Autodesk Fusion 360 part; units mm, degrees
(part 3 of 3)
sketch "Sketch9" plane through (0, 0, 32.4334) normal (0, 0, -1) x (1, 0, 0)
  circle A0 centre (290.8949, -267.5741) radius 1.5
  line L0 (337.7884, -328.2178) -> (337.7884, -325.2178)
  line L1 (337.7884, -325.2178) -> (343.7884, -325.2178)
  line L2 (343.7884, -325.2178) -> (343.7884, -322.2178)
  line L3 (343.7884, -322.2178) -> (349.7884, -322.2178)
  line L4 (349.7884, -322.2178) -> (349.7884, -319.2178)
  line L5 (349.7884, -319.2178) -> (358.7884, -319.2178)
  line L6 (358.7884, -319.2178) -> (358.7884, -316.2178)
  line L7 (358.7884, -316.2178) -> (370.7884, -316.2178)
  line L8 (370.7884, -316.2178) -> (370.7884, -313.2178)
  line L9 (370.7884, -313.2178) -> (408.7884, -313.2178)
  line L10 (408.7884, -313.2178) -> (408.7884, -316.2178)
  line L11 (408.7884, -316.2178) -> (420.7885, -316.2178)
  line L12 (420.7885, -316.2178) -> (420.7885, -319.2178)
  line L13 (420.7885, -319.2178) -> (429.7885, -319.2178)
  line L14 (429.7885, -319.2178) -> (429.7885, -322.2178)
  line L15 (429.7885, -322.2178) -> (435.7885, -322.2178)
  line L16 (435.7885, -322.2178) -> (435.7885, -325.2178)
  line L17 (435.7885, -325.2178) -> (441.7885, -325.2178)
  line L18 (441.7885, -325.2178) -> (441.7885, -328.2178)
  line L19 (441.7885, -328.2178) -> (444.7885, -328.2178)
  line L20 (444.7885, -328.2178) -> (444.7885, -331.2178)
  line L21 (444.7885, -331.2178) -> (459.7885, -331.2178)
  line L22 (459.7885, -331.2178) -> (459.7885, -328.2178)
  line L23 (459.7885, -328.2178) -> (462.7885, -328.2178)
  line L24 (462.7885, -328.2178) -> (462.7885, -325.2178)
  line L25 (462.7885, -325.2178) -> (465.7885, -325.2178)
  line L26 (465.7885, -325.2178) -> (465.7885, -319.2178)
  line L27 (465.7885, -319.2178) -> (468.7885, -319.2178)
  line L28 (468.7885, -319.2178) -> (468.7885, -310.2178)
  line L29 (468.7885, -310.2178) -> (471.7885, -310.2178)
  line L30 (471.7885, -310.2178) -> (471.7885, -307.2178)
  line L31 (471.7885, -307.2178) -> (474.7885, -307.2178)
  line L32 (474.7885, -307.2178) -> (474.7885, -304.2178)
  line L33 (474.7885, -304.2178) -> (477.7885, -304.2178)
  line L34 (477.7885, -304.2178) -> (477.7885, -298.2178)
  line L35 (477.7885, -298.2178) -> (480.7885, -298.2178)
  line L36 (480.7885, -298.2178) -> (480.7885, -289.2178)
  line L37 (480.7885, -289.2178) -> (483.7885, -289.2178)
  line L38 (483.7885, -289.2178) -> (483.7885, -277.2178)
  line L39 (483.7885, -277.2178) -> (486.7885, -277.2178)
  line L40 (486.7885, -277.2178) -> (486.7885, -256.2178)
  line L41 (486.7885, -256.2178) -> (489.7885, -256.2178)
  line L42 (489.7885, -256.2178) -> (489.7885, -238.2178)
  line L43 (489.7885, -238.2178) -> (486.7885, -238.2178)
  line L44 (486.7885, -238.2178) -> (486.7885, -229.2178)
  line L45 (486.7885, -229.2178) -> (483.7885, -229.2178)
  line L46 (483.7885, -229.2178) -> (483.7885, -226.2178)
  line L47 (483.7885, -226.2178) -> (480.7885, -226.2178)
  line L48 (480.7885, -226.2178) -> (480.7885, -223.2178)
  line L49 (480.7885, -223.2178) -> (477.7885, -223.2178)
  line L50 (477.7885, -223.2178) -> (477.7885, -220.2178)
  line L51 (477.7885, -220.2178) -> (459.7885, -220.2178)
  line L52 (459.7885, -220.2178) -> (459.7885, -223.2178)
  line L53 (459.7885, -223.2178) -> (456.7885, -223.2178)
  line L54 (456.7885, -223.2178) -> (456.7885, -226.2178)
  line L55 (456.7885, -226.2178) -> (453.7885, -226.2178)
  line L56 (453.7885, -226.2178) -> (453.7885, -229.2178)
  line L57 (453.7885, -229.2178) -> (450.7885, -229.2178)
  line L58 (450.7885, -229.2178) -> (450.7885, -232.2178)
  line L59 (450.7885, -232.2178) -> (447.7885, -232.2178)
  line L60 (447.7885, -232.2178) -> (447.7885, -238.2178)
  line L61 (447.7885, -238.2178) -> (444.7885, -238.2178)
  line L62 (444.7885, -238.2178) -> (444.7885, -244.2178)
  line L63 (444.7885, -244.2178) -> (441.7885, -244.2178)
  line L64 (441.7885, -244.2178) -> (441.7885, -247.2178)
  line L65 (441.7885, -247.2178) -> (438.7885, -247.2178)
  line L66 (438.7885, -247.2178) -> (438.7885, -250.2178)
  line L67 (438.7885, -250.2178) -> (435.7885, -250.2178)
  line L68 (435.7885, -250.2178) -> (435.7885, -253.2178)
  line L69 (435.7885, -253.2178) -> (343.7884, -253.2178)
  line L70 (343.7884, -253.2178) -> (343.7884, -250.2178)
  line L71 (343.7884, -250.2178) -> (340.7884, -250.2178)
  line L72 (340.7884, -250.2178) -> (340.7884, -247.2178)
  line L73 (340.7884, -247.2178) -> (337.7884, -247.2178)
  line L74 (337.7884, -247.2178) -> (337.7884, -244.2178)
  line L75 (337.7884, -244.2178) -> (334.7884, -244.2178)
  line L76 (334.7884, -244.2178) -> (334.7884, -238.2178)
  line L77 (334.7884, -238.2178) -> (331.7884, -238.2178)
  line L78 (331.7884, -238.2178) -> (331.7884, -232.2178)
  line L79 (331.7884, -232.2178) -> (328.7884, -232.2178)
  line L80 (328.7884, -232.2178) -> (328.7884, -229.2178)
  line L81 (328.7884, -229.2178) -> (325.7884, -229.2178)
  line L82 (325.7884, -229.2178) -> (325.7884, -226.2178)
  line L83 (325.7884, -226.2178) -> (322.7884, -226.2178)
  line L84 (322.7884, -226.2178) -> (322.7884, -223.2178)
  line L85 (322.7884, -223.2178) -> (319.7884, -223.2178)
  line L86 (319.7884, -223.2178) -> (319.7884, -220.2178)
  line L87 (319.7884, -220.2178) -> (301.7884, -220.2178)
  line L88 (301.7884, -220.2178) -> (301.7884, -223.2178)
  line L89 (301.7884, -223.2178) -> (298.7884, -223.2178)
  line L90 (298.7884, -223.2178) -> (298.7884, -226.2178)
  line L91 (298.7884, -226.2178) -> (295.7884, -226.2178)
  line L92 (295.7884, -226.2178) -> (295.7884, -229.2178)
  line L93 (295.7884, -229.2178) -> (292.7884, -229.2178)
  line L94 (292.7884, -229.2178) -> (292.7884, -238.2178)
  line L95 (292.7884, -238.2178) -> (289.7884, -238.2178)
  line L96 (289.7884, -238.2178) -> (289.7884, -256.2178)
  line L97 (289.7884, -256.2178) -> (292.7884, -256.2178)
  line L98 (292.7884, -256.2178) -> (292.7884, -266.2145)
  arc A1 (292.7884, -266.2145) -> (292.7884, -268.9337) centre (290.8949, -267.5741) ccw
  line L99 (292.7884, -268.9337) -> (292.7884, -277.2178)
  line L100 (292.7884, -277.2178) -> (295.7884, -277.2178)
  line L101 (295.7884, -277.2178) -> (295.7884, -289.2178)
  line L102 (295.7884, -289.2178) -> (298.7884, -289.2178)
  line L103 (298.7884, -289.2178) -> (298.7884, -298.2178)
  line L104 (298.7884, -298.2178) -> (301.7884, -298.2178)
  line L105 (301.7884, -298.2178) -> (301.7884, -304.2178)
  line L106 (301.7884, -304.2178) -> (304.7884, -304.2178)
  line L107 (304.7884, -304.2178) -> (304.7884, -307.2178)
  line L108 (304.7884, -307.2178) -> (307.7884, -307.2178)
  line L109 (307.7884, -307.2178) -> (307.7884, -310.2178)
  line L110 (307.7884, -310.2178) -> (310.7884, -310.2178)
  line L111 (310.7884, -310.2178) -> (310.7884, -319.2178)
  line L112 (310.7884, -319.2178) -> (313.7884, -319.2178)
  line L113 (313.7884, -319.2178) -> (313.7884, -325.2178)
  line L114 (313.7884, -325.2178) -> (316.7884, -325.2178)
  line L115 (316.7884, -325.2178) -> (316.7884, -328.2178)
  line L116 (316.7884, -328.2178) -> (319.7884, -328.2178)
  line L117 (319.7884, -328.2178) -> (319.7884, -331.2178)
  line L118 (319.7884, -331.2178) -> (334.7884, -331.2178)
  line L119 (334.7884, -331.2178) -> (334.7884, -328.2178)
  line L120 (334.7884, -328.2178) -> (337.7884, -328.2178)
  line L121 (336.7884, -324.2178) -> (336.7884, -327.2178)
  line L122 (336.7884, -327.2178) -> (333.7884, -327.2178)
  line L123 (333.7884, -327.2178) -> (333.7884, -330.2178)
  line L124 (333.7884, -330.2178) -> (320.7884, -330.2178)
  line L125 (320.7884, -330.2178) -> (320.7884, -327.2178)
  line L126 (320.7884, -327.2178) -> (317.7884, -327.2178)
  line L127 (317.7884, -327.2178) -> (317.7884, -324.2178)
  line L128 (317.7884, -324.2178) -> (314.7884, -324.2178)
  line L129 (314.7884, -324.2178) -> (314.7884, -318.2178)
  line L130 (314.7884, -318.2178) -> (311.7884, -318.2178)
  line L131 (311.7884, -318.2178) -> (311.7884, -309.2178)
  line L132 (311.7884, -309.2178) -> (308.7884, -309.2178)
  line L133 (308.7884, -309.2178) -> (308.7884, -306.2178)
  line L134 (308.7884, -306.2178) -> (305.7884, -306.2178)
  line L135 (305.7884, -306.2178) -> (305.7884, -303.2178)
  line L136 (305.7884, -303.2178) -> (302.7884, -303.2178)
  line L137 (302.7884, -303.2178) -> (302.7884, -297.2178)
  line L138 (302.7884, -297.2178) -> (299.7884, -297.2178)
  line L139 (299.7884, -297.2178) -> (299.7884, -288.2178)
  line L140 (299.7884, -288.2178) -> (296.7884, -288.2178)
  line L141 (296.7884, -288.2178) -> (296.7884, -276.2178)
  line L142 (296.7884, -276.2178) -> (293.7884, -276.2178)
  line L143 (293.7884, -276.2178) -> (293.7884, -255.2178)
  line L144 (293.7884, -255.2178) -> (290.7884, -255.2178)
  line L145 (290.7884, -255.2178) -> (290.7884, -239.2178)
  line L146 (290.7884, -239.2178) -> (293.7884, -239.2178)
  line L147 (293.7884, -239.2178) -> (293.7884, -230.2178)
  line L148 (293.7884, -230.2178) -> (296.7884, -230.2178)
  line L149 (296.7884, -230.2178) -> (296.7884, -227.2178)
  line L150 (296.7884, -227.2178) -> (299.7884, -227.2178)
  line L151 (299.7884, -227.2178) -> (299.7884, -224.2178)
  line L152 (299.7884, -224.2178) -> (302.7884, -224.2178)
  line L153 (302.7884, -224.2178) -> (302.7884, -221.2178)
  line L154 (302.7884, -221.2178) -> (318.7884, -221.2178)
  line L155 (318.7884, -221.2178) -> (318.7884, -224.2178)
  line L156 (318.7884, -224.2178) -> (321.7884, -224.2178)
  line L157 (321.7884, -224.2178) -> (321.7884, -227.2178)
  line L158 (321.7884, -227.2178) -> (324.7884, -227.2178)
  line L159 (324.7884, -227.2178) -> (324.7884, -230.2178)
  line L160 (324.7884, -230.2178) -> (327.7884, -230.2178)
  line L161 (327.7884, -230.2178) -> (327.7884, -233.2178)
  line L162 (327.7884, -233.2178) -> (330.7884, -233.2178)
  line L163 (330.7884, -233.2178) -> (330.7884, -239.2178)
  line L164 (330.7884, -239.2178) -> (333.7884, -239.2178)
  line L165 (333.7884, -239.2178) -> (333.7884, -245.2178)
  line L166 (333.7884, -245.2178) -> (336.7884, -245.2178)
  line L167 (336.7884, -245.2178) -> (336.7884, -248.2178)
  line L168 (336.7884, -248.2178) -> (339.7884, -248.2178)
  line L169 (339.7884, -248.2178) -> (339.7884, -251.2178)
  line L170 (339.7884, -251.2178) -> (342.7884, -251.2178)
  line L171 (342.7884, -251.2178) -> (342.7884, -254.2178)
  line L172 (342.7884, -254.2178) -> (436.7885, -254.2178)
  line L173 (436.7885, -254.2178) -> (436.7885, -251.2178)
  line L174 (436.7885, -251.2178) -> (439.7885, -251.2178)
  line L175 (439.7885, -251.2178) -> (439.7885, -248.2178)
  line L176 (439.7885, -248.2178) -> (442.7885, -248.2178)
  line L177 (442.7885, -248.2178) -> (442.7885, -245.2178)
  line L178 (442.7885, -245.2178) -> (445.7885, -245.2178)
  line L179 (445.7885, -245.2178) -> (445.7885, -239.2178)
  line L180 (445.7885, -239.2178) -> (448.7885, -239.2178)
  line L181 (448.7885, -239.2178) -> (448.7885, -233.2178)
  line L182 (448.7885, -233.2178) -> (451.7885, -233.2178)
  line L183 (451.7885, -233.2178) -> (451.7885, -230.2178)
  line L184 (451.7885, -230.2178) -> (454.7885, -230.2178)
  line L185 (454.7885, -230.2178) -> (454.7885, -227.2178)
  line L186 (454.7885, -227.2178) -> (457.7885, -227.2178)
  line L187 (457.7885, -227.2178) -> (457.7885, -224.2178)
  line L188 (457.7885, -224.2178) -> (460.7885, -224.2178)
  line L189 (460.7885, -224.2178) -> (460.7885, -221.2178)
  line L190 (460.7885, -221.2178) -> (476.7885, -221.2178)
  line L191 (476.7885, -221.2178) -> (476.7885, -224.2178)
  line L192 (476.7885, -224.2178) -> (479.7885, -224.2178)
  line L193 (479.7885, -224.2178) -> (479.7885, -227.2178)
  line L194 (479.7885, -227.2178) -> (482.7885, -227.2178)
  line L195 (482.7885, -227.2178) -> (482.7885, -230.2178)
  line L196 (482.7885, -230.2178) -> (485.7885, -230.2178)
  line L197 (485.7885, -230.2178) -> (485.7885, -239.2178)
  line L198 (485.7885, -239.2178) -> (488.7885, -239.2178)
  line L199 (488.7885, -239.2178) -> (488.7885, -255.2178)
  line L200 (488.7885, -255.2178) -> (485.7885, -255.2178)
  line L201 (485.7885, -255.2178) -> (485.7885, -276.2178)
  line L202 (485.7885, -276.2178) -> (482.7885, -276.2178)
  line L203 (482.7885, -276.2178) -> (482.7885, -288.2178)
  line L204 (482.7885, -288.2178) -> (479.7885, -288.2178)
  line L205 (479.7885, -288.2178) -> (479.7885, -297.2178)
  line L206 (479.7885, -297.2178) -> (476.7885, -297.2178)
  line L207 (476.7885, -297.2178) -> (476.7885, -303.2178)
  line L208 (476.7885, -303.2178) -> (473.7885, -303.2178)
  line L209 (473.7885, -303.2178) -> (473.7885, -306.2178)
  line L210 (473.7885, -306.2178) -> (470.7885, -306.2178)
  line L211 (470.7885, -306.2178) -> (470.7885, -309.2178)
  line L212 (470.7885, -309.2178) -> (467.7885, -309.2178)
  line L213 (467.7885, -309.2178) -> (467.7885, -318.2178)
  line L214 (467.7885, -318.2178) -> (464.7885, -318.2178)
  line L215 (464.7885, -318.2178) -> (464.7885, -324.2178)
  line L216 (464.7885, -324.2178) -> (461.7885, -324.2178)
  line L217 (461.7885, -324.2178) -> (461.7885, -327.2178)
  line L218 (461.7885, -327.2178) -> (458.7885, -327.2178)
  line L219 (458.7885, -327.2178) -> (458.7885, -330.2178)
  line L220 (458.7885, -330.2178) -> (445.7885, -330.2178)
  line L221 (445.7885, -330.2178) -> (445.7885, -327.2178)
  line L222 (445.7885, -327.2178) -> (442.7885, -327.2178)
  line L223 (442.7885, -327.2178) -> (442.7885, -324.2178)
  line L224 (442.7885, -324.2178) -> (436.7885, -324.2178)
  line L225 (436.7885, -324.2178) -> (436.7885, -321.2178)
  line L226 (436.7885, -321.2178) -> (430.7885, -321.2178)
  line L227 (430.7885, -321.2178) -> (430.7885, -318.2178)
  line L228 (430.7885, -318.2178) -> (421.7885, -318.2178)
  line L229 (421.7885, -318.2178) -> (421.7885, -315.2178)
  line L230 (421.7885, -315.2178) -> (409.7884, -315.2178)
  line L231 (409.7884, -315.2178) -> (409.7884, -312.2178)
  line L232 (409.7884, -312.2178) -> (369.7884, -312.2178)
  line L233 (369.7884, -312.2178) -> (369.7884, -315.2178)
  line L234 (369.7884, -315.2178) -> (357.7884, -315.2178)
  line L235 (357.7884, -315.2178) -> (357.7884, -318.2178)
  line L236 (357.7884, -318.2178) -> (348.7884, -318.2178)
  line L237 (348.7884, -318.2178) -> (348.7884, -321.2178)
  line L238 (348.7884, -321.2178) -> (342.7884, -321.2178)
  line L239 (342.7884, -321.2178) -> (342.7884, -324.2178)
  line L240 (342.7884, -324.2178) -> (336.7884, -324.2178)
  circle A2 centre (488.7064, -265.5035) radius 1.5
  circle A3 centre (488.7064, -265.5035) radius 2.302
  dimension "d32" = 3
  constraint concentric A2 A3
  measures "d32" diameter of A2
extrude "Extrude10" add sketch "Sketch9" against normal blind 4 contours L40 A3 picked at (486.9278, -265.5035) bodies 2
